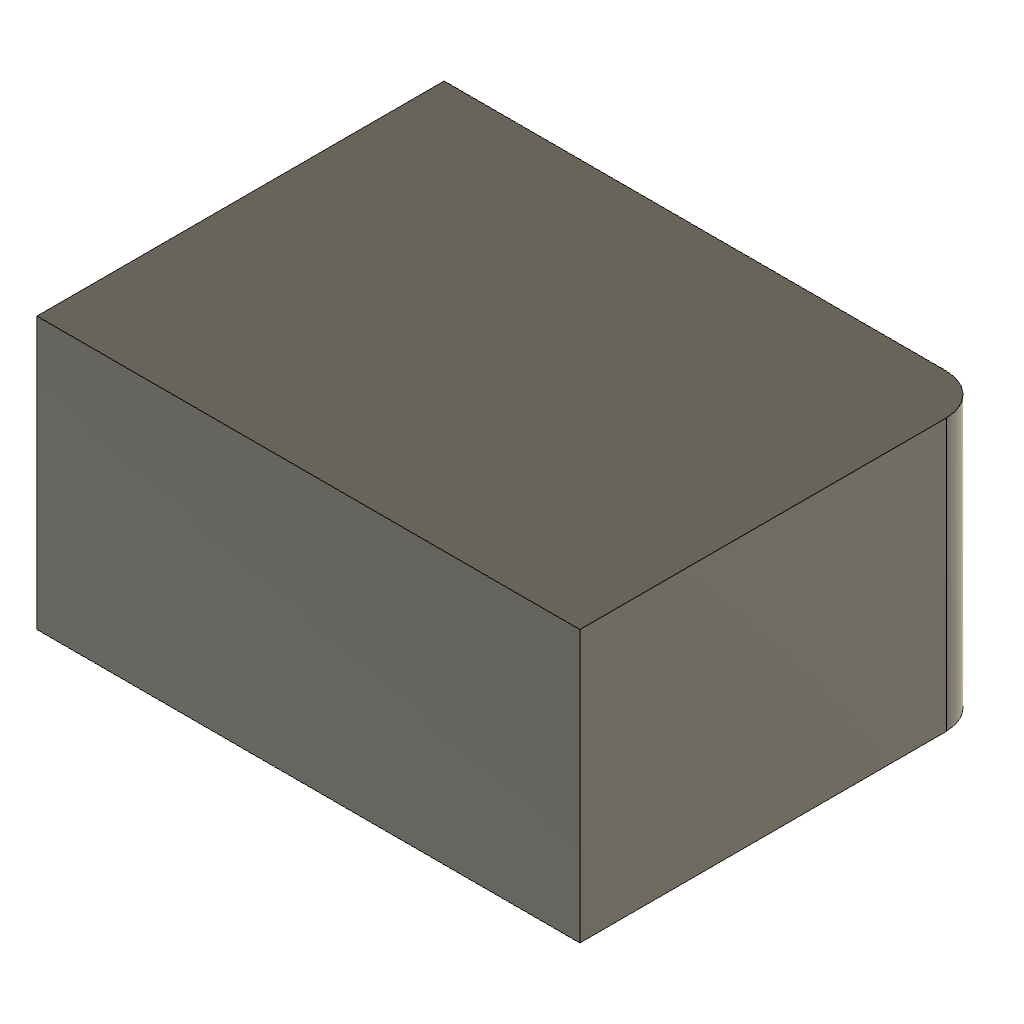
FilletDirtyEdited (Autodesk Fusion 360 design; units mm, degrees)
part number: 2026-11-12-11-46-33-989
Autodesk Fusion 360 part; units mm, degrees
sketch "Base sketch" plane through (0, 0, 0) normal (0, 0, 1) x (1, 0, 0)
  line L0 (0, 0) -> (40, 0)
  line L1 (40, 0) -> (40, 30)
  line L2 (40, 30) -> (0, 30)
  line L3 (0, 30) -> (0, 0)
extrude "Base extrude" add sketch "Base sketch" along normal blind 20
fillet "Corner fillet" [rolled back] radius 3
